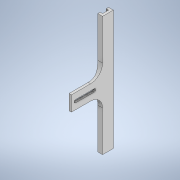
# Autodesk Inventor part: culise_usa_triunghi
Saved by Autodesk Inventor 2022.6 (Build 266554000, 554)
## iProperties
Created: 2025-09-02
Part Number: culise_usa_triunghi
Material: Generic
Document SubType Name: Modeling
Designer: Dragos Macovei
Density: 1 g/cm^3
Appearance: Default
Author: Dragos Macovei
Autodesk Inventor part; units mm, degrees
ref_plane "YZ Plane" through (0, 0, 0) normal (1, 0, 0) x (0, 1, 0)
ref_plane "XZ Plane" through (0, 0, 0) normal (0, 1, 0) x (-1, 0, 0)
ref_plane "XY Plane" through (0, 0, 0) normal (0, 0, 1) x (1, 0, 0)
sketch "Sketch1" plane through (0, 0, 0) normal (0, 1, 0) x (-1, 0, 0)
  line L0 (8, 15.635) -> (4, 15.635)
  line L1 (4, 15.635) -> (4, 5.635)
  line L2 (4, 5.635) -> (8, 5.635)
  line L3 (8, 5.635) -> (8, 1.635)
  line L4 (8, 1.635) -> (0, 1.635)
  line L5 (0, 1.635) -> (0, 19.635)
  line L6 (0, 19.635) -> (8, 19.635)
  line L7 (8, 19.635) -> (8, 15.635)
  point P0 (0, 0)
  point P1 (4, 10.635)
  dimension "d0" = 4
  dimension "d1" = 4
  dimension "d2" = 4
  dimension "d3" = 10
  dimension "d4" = 4
  constraints: 16 end point, 7 perpendicular, 1 horizontal, 1 midpoint, 1 point on line
  measures "d0" distance between parallel lines of L6 L0
  measures "d1" distance between parallel lines of L4 L2
  measures "d2" distance from line of L5 point (4, 10.635)
  measures "d3" distance between parallel lines of L2 L0
  measures "d4" distance between parallel lines of L1 L7
extrude "Extrusion1" add sketch "Sketch1" along normal blind 200
sketch "Sketch2" plane through (0, 0, 19.635) normal (1, 0, 0) x (0, 0, -1)
  line L0 (14, 0) -> (14, 200) projected
  line L1 (4, 0) -> (4, 200) projected
  line L2 (0, 0) -> (18, 0) projected
  line L3 (18, 0) -> (18, 200) projected
  line L4 (0, 200) -> (18, 200) projected
  line L5 (0, 0) -> (0, 200) projected
  line L6 (0, 0) -> (0, 200) projected
  line L7 (18, 0) -> (18, 200) projected
  line L8 (18, 87.5) -> (-52, 87.5)
  line L9 (-52, 87.5) -> (-52, 112.5)
  line L10 (-52, 112.5) -> (18, 112.5)
  line L11 (18, 112.5) -> (18, 87.5)
  point P0 (19.635, 0)
  point P1 (0, 100)
  point P2 (-17, 112.5)
  point P3 (0, 87.5)
  point P4 (0, 112.5)
  point P5 (18, 112.5)
  point P6 (14, 112.5)
  point P7 (14, 87.5)
  point P8 (4, 112.5)
  point P9 (4, 87.5)
  point P10 (0, 87.5)
  point P11 (0, 112.5)
  dimension "d7" = 70
  dimension "d8" = 25
  dimension "d9" = 12.5
  constraints: 8 end point, 2 midpoint, 2 parallel, 1 horizontal, 1 perpendicular, 1 point on line
  measures "d7" distance between parallel lines of L9 L3
  measures "d8" distance between parallel lines of L8 L10
  measures "d9" vertical distance of point (0, 100) point (-17, 112.5)
extrude "Extrusion2" add sketch "Sketch2" against normal blind 4 contours L8 L9 L10 L5
fillet "Fillet1" radius 20 3 edges at (-2, 112.5, 19.635) (-4, 100, 19.635) (-2, 87.5, 19.635)
sketch "Sketch3" plane through (-4, 0, 19.635) normal (-1, 0, 0) x (0, 0, 1)
  line L0 (12, 85.8303) -> (12, 114.1697) projected
  arc A0 (20, 87.5) -> (12, 85.8303) centre (20, 67.5) ccw projected
  line L1 (20, 87.5) -> (52, 87.5) projected
  line L2 (52, 87.5) -> (52, 112.5) projected
  line L3 (52, 112.5) -> (20, 112.5) projected
  arc A1 (12, 114.1697) -> (20, 112.5) centre (20, 132.5) ccw projected
  circle A2 centre (14, 100) radius 2.5
  circle A3 centre (45, 100) radius 2.5
  line L4 (0, 67.5) -> (0, 132.5) projected
  line L5 (12, 85.8303) -> (12, 114.1697) projected
  line L6 (14, 102.5) -> (45, 102.5)
  line L7 (45, 97.5) -> (14, 97.5)
  point P0 (-19.635, 0)
  point P1 (52, 100)
  point P2 (0, 100)
  point P3 (12, 100)
  point P4 (12, 101.5)
  point P5 (12, 98.5)
  dimension "d13" = 5
  dimension "d14" = 7
  dimension "d16" = 2
  constraints: 4 end point, 4 point on circle, 3 midpoint, 2 centre point, 1 parallel, 1 tangent
  measures "d13" diameter of A2
  measures "d14" distance of point (52, 100) A3.centre
  measures "d16" distance of point (12, 100) A2.centre
extrude "Extrusion3" cut sketch "Sketch3" against normal through all contours L0 A2 | A2 L6 A3 L7 | A3 picked at (14.1367, 100.6515)
equation "\"d1\" = d0"
equation "\"d2\" = d1"
equation "\"d9\" = 0.5 * d8"
body "Solid1"
